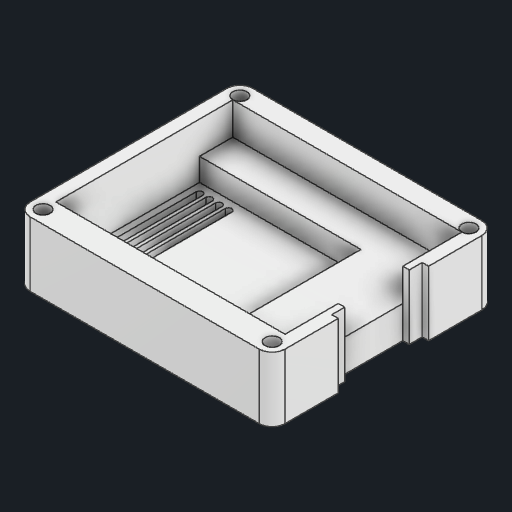
# Autodesk Inventor part: D1 CASE
Saved by Autodesk Inventor 2027.1 (Build 311270010, 270A)
## iProperties
Created: 2026-09-25
Part Number: D1 CASE
Material: ABS 플라스틱
Document SubType Name: Modeling
Designer: work
Density: 1.06 g/cm^3
Appearance: 매끄러움 - 흰색
Author: work
Autodesk Inventor part; units mm, degrees
ref_plane "YZ Plane" through (0, 0, 0) normal (1, 0, 0) x (0, 1, 0)
ref_plane "XZ Plane" through (0, 0, 0) normal (0, 1, 0) x (-1, 0, 0)
ref_plane "XY Plane" through (0, 0, 0) normal (0, 0, 1) x (1, 0, 0)
sketch "스케치1" plane through (0, 0, 0) normal (0, 1, 0) x (-1, 0, 0)
  line L0 (0, 0) -> (35.5, 0)
  line L1 (35.5, 0) -> (35.5, -26.5)
  line L2 (35.5, -26.5) -> (0, -26.5)
  line L3 (0, -26.5) -> (0, 0)
  line L4 (37.5, -28.5) -> (37.5, 2)
  line L5 (37.5, 2) -> (-2, 2) construction
  line L6 (-2, 2) -> (-2, -28.5)
  line L7 (-2, -28.5) -> (37.5, -28.5) construction
  circle A0 centre (35.5, 2) radius 1.1
  circle A1 centre (35.5, 2) radius 2
  circle A2 centre (0, 2) radius 1.1
  circle A3 centre (0, 2) radius 2
  line L8 (0, 4) -> (35.5, 4)
  line L9 (-2, -13.25) -> (37.5, -13.25) construction
  line L10 (0, -26.5) -> (35.5, -26.5)
  line L11 (35.5, -26.5) -> (35.5, 0)
  line L12 (0, 0) -> (0, -26.5)
  line L13 (37.5, 2) -> (37.5, -28.5)
  line L14 (37.5, -28.5) -> (-2, -28.5) construction
  line L15 (-2, -28.5) -> (-2, 2)
  circle A4 centre (35.5, -28.5) radius 1.1
  circle A5 centre (35.5, -28.5) radius 2
  circle A6 centre (0, -28.5) radius 1.1
  circle A7 centre (0, -28.5) radius 2
  line L16 (0, -30.5) -> (35.5, -30.5)
  line L17 (0, -8.25) -> (-2, -8.25)
  line L18 (-2, -8.25) -> (-2, -18.25)
  line L19 (-2, -18.25) -> (0, -18.25)
  line L20 (0, -18.25) -> (0, -8.25)
  line L21 (-2, -6.25) -> (-1, -6.25)
  line L22 (-1, -6.25) -> (-1, -20.25)
  line L23 (-1, -20.25) -> (-2, -20.25)
  line L24 (-2, -20.25) -> (-2, -6.25)
  point P0 (0, -13.25)
  point P1 (-2, -13.25)
  point P2 (-1, -13.25)
  point P3 (-1, -8.25)
  point P4 (-1, -18.25)
  dimension "d0" = 35.5
  dimension "d1" = 26.5
  dimension "d2" = 2
  dimension "d3" = 2.2
  dimension "d4" = 2.2
  dimension "d5" = 10
  dimension "d6" = 1
  dimension "d7" = 14
  constraints: 50 end point, 14 symmetric about line, 8 centre point, 8 parallel, 8 point on circle, 7 midpoint, 6 point on line, 4 coincident, 4 perpendicular, 3 horizontal, 2 tangent, 2 vertical alignment, 7 other
  measures "d0" distance of L1.end L2.end
  measures "d1" distance of L0.end L1.end
  measures "d2" distance between parallel lines of L1 L4
  measures "d3" diameter of A0
  measures "d4" diameter of A2
  measures "d5" distance of L17.end L18.end
  measures "d6" distance between parallel lines of L3 L22
  measures "d7" distance of L21.end L22.end
extrude "돌출1" add sketch "스케치1" along normal blind 10 contours A3 L8 A1 L0 | L3 L17 L22 L21 L6 A3 | A3 | A1 L4 A5 L1 | A1 | A5 L16 A7 L2 | A5 | L3 A7 L6 L23 L22 L19 | A7
extrude "돌출2" add sketch "스케치1" along normal blind 5 contours L0 L1 L2 L3 | A0 | A2 | A4 | A6
sketch "스케치2" plane through (0, 5, 0) normal (0, 1, 0) x (1, 0, 0)
  line L0 (-35.5, 4.25) -> (-10.5, 4.25)
  line L1 (-10.5, 4.25) -> (-10.5, 22.25)
  line L2 (-10.5, 22.25) -> (-35.5, 22.25)
  line L3 (-35.5, 22.25) -> (-35.5, 4.25)
  line L4 (-35.5, 0) -> (-35.5, 26.5) projected
  point P0 (0, 0)
  point P1 (-35.5, 13.25)
  dimension "d12" = 25
  dimension "d13" = 18
  constraints: 8 end point, 2 midpoint, 2 parallel, 1 horizontal, 1 perpendicular
  measures "d12" distance of L0.start L0.end
  measures "d13" distance of L0.end L1.end
extrude "돌출3" cut sketch "스케치2" against normal blind 3.5
sketch "스케치3" plane through (0, 10, 0) normal (0, 1, 0) x (1, 0, 0)
  line L0 (-35.5, 26.5) -> (0, 26.5) projected
  circle A0 centre (-35.5, 28.5) radius 1.1 projected
  line L1 (0, 26.5) -> (-35.5, 26.5)
  line L2 (-35.5, 26.5) -> (-35.5, 27.4)
  line L3 (-35.5, 27.4) -> (0, 27.4)
  line L4 (0, 27.4) -> (0, 26.5)
  point P0 (0, 0)
  constraints: 8 end point, 2 parallel, 1 horizontal, 1 perpendicular, 1 vertical alignment, 1 other
extrude "돌출4" cut sketch "스케치3" against normal up to surface (5 mm away) contours L2 L3 L4 L0
sketch "스케치4" plane through (0, 1.5, 0) normal (0, 1, 0) x (1, 0, 0)
  line L0 (-35.5, 4.25) -> (-35.5, 22.25) projected
  line L1 (-35.5, 13.25) -> (-10.5, 13.25) construction
  line L2 (-10.5, 22.25) -> (-10.5, 4.25) projected
  line L3 (-34, 5.75) -> (-34, 20.75) construction
  line L4 (-33.5, 5.75) -> (-33.5, 20.75)
  line L5 (-34.5, 20.75) -> (-34.5, 5.75)
  arc A0 (-34.5, 5.75) -> (-33.5, 5.75) centre (-34, 5.75) ccw
  arc A1 (-33.5, 20.75) -> (-34.5, 20.75) centre (-34, 20.75) ccw
  line L6 (-35.5, 22.25) -> (-10.5, 22.25) projected
  line L7 (-32.5, 5.75) -> (-32.5, 20.75) construction
  line L8 (-32, 5.75) -> (-32, 20.75)
  line L9 (-33, 20.75) -> (-33, 5.75)
  arc A2 (-33, 5.75) -> (-32, 5.75) centre (-32.5, 5.75) ccw
  arc A3 (-32, 20.75) -> (-33, 20.75) centre (-32.5, 20.75) ccw
  line L10 (-31, 5.75) -> (-31, 20.75) construction
  line L11 (-30.5, 5.75) -> (-30.5, 20.75)
  line L12 (-31.5, 20.75) -> (-31.5, 5.75)
  arc A4 (-31.5, 5.75) -> (-30.5, 5.75) centre (-31, 5.75) ccw
  arc A5 (-30.5, 20.75) -> (-31.5, 20.75) centre (-31, 20.75) ccw
  line L13 (-29.5, 5.75) -> (-29.5, 20.75) construction
  line L14 (-29, 5.75) -> (-29, 20.75)
  line L15 (-30, 20.75) -> (-30, 5.75)
  arc A6 (-30, 5.75) -> (-29, 5.75) centre (-29.5, 5.75) ccw
  arc A7 (-29, 20.75) -> (-30, 20.75) centre (-29.5, 20.75) ccw
  point P0 (0, 0)
  point P1 (-34, 13.25)
  point P2 (-34, 21.25)
  point P3 (-32.5, 21.25)
  point P4 (-31, 21.25)
  point P5 (-29.5, 21.25)
  dimension "d18" = 1
  dimension "d19" = 1
  dimension "d20" = 1
  dimension "d23" = 1.5
  constraints: 34 end point, 17 point on circle, 8 centre point, 4 tangent, 3 midpoint, 1 horizontal, 1 parallel, 1 perpendicular, 1 point on line, 36 other
  measures "d18" distance from line of L6 point (-34, 21.25)
  measures "d19" distance between parallel lines of L0 L5
  measures "d20" distance between parallel lines of L4 L5
  measures "d23" distance of L3.start L7.start
extrude "돌출5" cut sketch "스케치4" against normal blind 10
